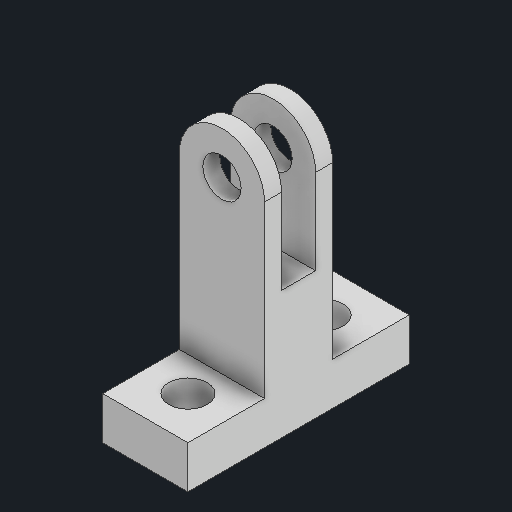
# Autodesk Inventor part: support_de_maintient_incline_tuyau
Saved by Autodesk Inventor 2026 (Build 300175000, 175)
## iProperties
Created: 2025-05-04
Part Number: support_de_maintient_incline_tuyau
Material: Générique
Document SubType Name: Modeling
Designer: virgi
Density: 1 g/cm^3
Appearance: Par défaut
Author: virgi
Autodesk Inventor part; units mm, degrees
ref_plane "YZ Plane" through (0, 0, 0) normal (1, 0, 0) x (0, 1, 0)
sketch "Esquisse1" plane through (0, 0, 0) normal (1, 0, 0) x (0, 1, 0)
  line L0 (0, 0) -> (0, 13)
  line L1 (0, 13) -> (5, 13)
  line L2 (5, 13) -> (5, 4)
  line L3 (49.0161, 0) -> (-8.2272, 0)
  line L4 (0, 0) -> (0, -13)
  line L5 (0, -13) -> (5, -13)
  line L6 (5, -13) -> (5, -4)
  line L7 (5, -4) -> (30, -4)
  line L8 (5, 4) -> (30, 4)
  line L9 (30, 4) -> (30, 2)
  line L10 (30, 2) -> (15, 2)
  line L11 (15, 2) -> (15, -2)
  line L12 (15, -2) -> (30, -2)
  line L13 (30, -2) -> (30, -4)
  point P0 (5, 8.5)
  point P1 (2.5, 13)
  point P2 (17.5, 4)
  point P3 (22.5, 2)
  dimension "d2" = 5
  dimension "d3" = 26
  dimension "d11" = 8
  dimension "d12" = 2
  dimension "d13" = 30
  dimension "d15" = 15
  constraints: 28 end point, 6 perpendicular, 4 midpoint, 3 symmetric about line, 2 horizontal, 2 point on line, 2 vertical, 1 other
  measures "d2" distance from line of L0 point (5, 8.5)
  measures "d3" diameter of point (2.5, 13) L3
  measures "d11" distance between parallel lines of L8 L7
  measures "d12" distance from line of L8 point (22.5, 2)
  measures "d13" distance between parallel lines of L0 L9
  measures "d15" distance between parallel lines of L13 L11
extrude "Extrusion1" add sketch "Esquisse1" along normal blind 10
ref_plane "Plan de construction" through (5, 0, 0) normal (1, 0, 0) x (0, 0, -1)
sketch "Esquisse4" plane through (0, 5, 4) normal (0, 0, 1) x (1, 0, 0)
  line L0 (5, 49) -> (5, -14) projected
  line L1 (0, 25) -> (10, 25) projected
  point P0 (0, -5)
  point P1 (5, 20)
  dimension "d23" = 5
  constraints: 1 point on line
  measures "d23" distance from line of L1 point (5, 20)
hole "Perçage1" at (5, 25, 4) direction (0, 0, -1) diameter 4.5 end through all
fillet "Congé1" radius 5 4 edges at (10, 30, -3) (10, 30, 3) (0, 30, 3) (0, 30, -3)
ref_plane "Plan de construction4" through (0, 5, 0) normal (0, 0, 1) x (1, 0, 0)
sketch "Esquisse5" plane through (0, 0, -13) normal (0, -1, 0) x (1, 0, 0)
  line L0 (5, 31.2) -> (5, -5.2) projected
  line L1 (-2, 13) -> (12, 13) projected
  point P0 (0, 13)
  point P1 (5, 21)
  point P2 (5, 5)
  dimension "d32" = 8
  constraints: 1 point on line, 1 symmetric about line
  measures "d32" distance from line of L1 point (5, 21)
hole "Perçage2" at (5, 0, 8) at (5, 0, -8) direction (0, 1, 0) diameter 4.5 end through all
